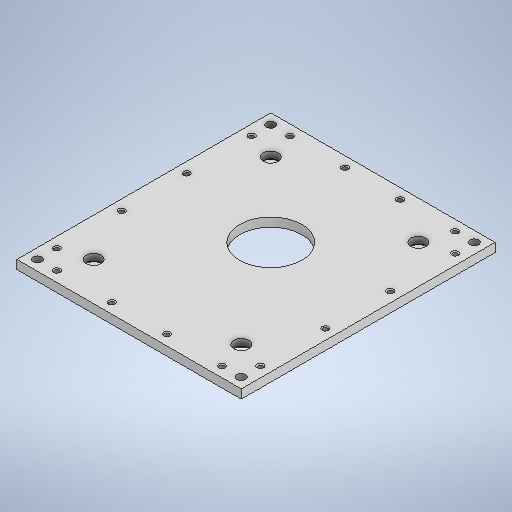
# Autodesk Inventor part: płyta_przednia
Saved by Autodesk Inventor 2025.2 (Build 292293000, 293)
## iProperties
Created: 2025-04-07
Part Number: płyta_przednia
Material: Ogólny
Document SubType Name: Modeling
Designer: Jan Bołtralik
Density: 1 g/cm^3
Appearance: Domyślna
Author: Jan Bołtralik
Autodesk Inventor part; units mm, degrees
ref_plane "YZ Plane" through (0, 0, 0) normal (1, 0, 0) x (0, 1, 0)
ref_plane "XZ Plane" through (0, 0, 0) normal (0, 1, 0) x (-1, 0, 0)
ref_plane "XY Plane" through (0, 0, 0) normal (0, 0, 1) x (1, 0, 0)
sketch "Szkic1" plane through (0, 0, 0) normal (0, 1, 0) x (-1, 0, 0)
  line L0 (0, 0) -> (-76, 0)
  line L1 (-76, 0) -> (-76, -86)
  line L2 (-76, -86) -> (0, -86)
  line L3 (0, -86) -> (0, 0)
  circle A0 centre (-38, -48) radius 10.5
  line L4 (-63, -13) -> (-13, -13) construction
  line L5 (-13, -13) -> (-13, -73) construction
  line L6 (-13, -73) -> (-63, -73) construction
  line L7 (-63, -73) -> (-63, -13) construction
  dimension "d23" = 76
  dimension "d24" = 86
  dimension "d25" = 21
  dimension "d26" = 38
  dimension "d27" = 38
  dimension "d28" = 50
  dimension "d29" = 60
  dimension "d30" = 13
  dimension "d31" = 13
  constraints: 16 end point, 4 parallel, 2 horizontal, 2 perpendicular, 1 centre point, 1 other
  measures "d23" distance of L2.end L1.end
  measures "d24" distance of L1.end L0.end
  measures "d25" diameter of A0
  measures "d26" distance from line of L3 A0.centre
  measures "d27" distance from line of L2 A0.centre
  measures "d28" distance of L5.end L6.end
  measures "d29" distance of L4.end L5.end
  measures "d30" distance between parallel lines of L2 L6
  measures "d31" distance between parallel lines of L1 L7
extrude "Wyciągnięcie proste1" add sketch "Szkic1" along normal blind 3
sketch "Szkic2" plane through (0, 0, 0) normal (0, -1, 0) x (1, 0, 0)
  line L0 (76, 0) -> (76, -86) construction
  line L1 (0, 0) -> (76, 0) construction
  line L2 (0, -86) -> (0, 0) construction
  line L3 (76, -86) -> (0, -86) construction
  circle A0 centre (38, -48) radius 10.5 construction
  line L4 (63, -13) -> (13, -13) construction
  line L5 (13, -13) -> (13, -73) construction
  line L6 (13, -73) -> (63, -73) construction
  line L7 (63, -73) -> (63, -13) construction
  dimension "d32" = 50
  dimension "d33" = 60
  dimension "d34" = 13
  dimension "d35" = 13
  constraints: 8 end point, 2 parallel, 1 horizontal, 1 perpendicular
  measures "d32" distance of L6.end L5.end
  measures "d33" distance of L5.end L4.end
  measures "d34" distance between parallel lines of L3 L6
  measures "d35" distance between parallel lines of L2 L5
hole "Otwór2" at (63, 0, -13) at (63, 0, -73) at (13, 0, -13) at (13, 0, -73) direction (0, 1, 0) diameter 5 end through all countersink diameter 6.5 countersink angle 90
sketch "Szkic5" plane through (0, 3, 0) normal (0, 1, 0) x (1, 0, 0)
  circle A0 centre (10, 3.5) radius 1.1 projected
  circle A1 centre (10, 82.5) radius 1.1 projected
  circle A2 centre (28.6667, 3.5) radius 1.1 projected
  circle A3 centre (28.6667, 82.5) radius 1.1 projected
  circle A4 centre (47.3333, 3.5) radius 1.1 projected
  circle A5 centre (47.3333, 82.5) radius 1.1 projected
  circle A6 centre (66, 3.5) radius 1.1 projected
  circle A7 centre (66, 82.5) radius 1.1 projected
  circle A8 centre (72.5, 10) radius 1.1 projected
  circle A9 centre (3.5, 10) radius 1.1 projected
  circle A10 centre (72.5, 32) radius 1.1 projected
  circle A11 centre (3.5, 32) radius 1.1 projected
  circle A12 centre (72.5, 54) radius 1.1 projected
  circle A13 centre (3.5, 54) radius 1.1 projected
  circle A14 centre (72.5, 76) radius 1.1 projected
  circle A15 centre (3.5, 76) radius 1.1 projected
  arc A16 (0, 10) -> (10, 0) centre (10, 10) ccw projected
  line L0 (66, 0) -> (10, 0) projected
  arc A17 (66, 0) -> (76, 10) centre (66, 10) ccw projected
  line L1 (76, 76) -> (76, 10) projected
  arc A18 (76, 76) -> (66, 86) centre (66, 76) ccw projected
  line L2 (10, 86) -> (66, 86) projected
  arc A19 (10, 86) -> (0, 76) centre (10, 76) ccw projected
  line L3 (0, 10) -> (0, 76) projected
  line L4 (6.5, 76) -> (6.5, 10) projected
  arc A20 (10, 79.5) -> (6.5, 76) centre (10, 76) ccw projected
  line L5 (66, 79.5) -> (10, 79.5) projected
  arc A21 (69.5, 76) -> (66, 79.5) centre (66, 76) ccw projected
  line L6 (69.5, 10) -> (69.5, 76) projected
  arc A22 (66, 6.5) -> (69.5, 10) centre (66, 10) ccw projected
  line L7 (10, 6.5) -> (66, 6.5) projected
  arc A23 (6.5, 10) -> (10, 6.5) centre (10, 10) ccw projected
hole "Otwór5" at (66, 3, -82.5) at (47.3333, 3, -82.5) at (28.6667, 3, -82.5) at (10, 3, -82.5) at (3.5, 3, -76) at (3.5, 3, -54) at (3.5, 3, -32) at (3.5, 3, -10) at (10, 3, -3.5) at (28.6667, 3, -3.5) at (47.3333, 3, -3.5) at (66, 3, -3.5) at (72.5, 3, -10) at (72.5, 3, -32) at (72.5, 3, -54) at (72.5, 3, -76) direction (0, -1, 0) diameter 1.567 depth 6.3 countersink diameter 2.2 countersink angle 90 thread size "M2x0.4" class "6H" standard "ISO Metric profile"
sketch "Sketch6" plane through (0, 0, 0) normal (0, -1, 0) x (1, 0, 0)
  circle A0 centre (72.5, -76) radius 0.7835 projected
  circle A1 centre (72.5, -54) radius 0.7835 projected
  circle A2 centre (72.5, -32) radius 0.7835 projected
  circle A3 centre (72.5, -10) radius 0.7835 projected
  circle A4 centre (66, -3.5) radius 0.7835 projected
  circle A5 centre (47.3333, -3.5) radius 0.7835 projected
  circle A6 centre (28.6667, -3.5) radius 0.7835 projected
  circle A7 centre (10, -3.5) radius 0.7835 projected
  circle A8 centre (3.5, -10) radius 0.7835 projected
  circle A9 centre (3.5, -32) radius 0.7835 projected
  circle A10 centre (3.5, -54) radius 0.7835 projected
  circle A11 centre (3.5, -76) radius 0.7835 projected
  circle A12 centre (10, -82.5) radius 0.7835 projected
  circle A13 centre (28.6667, -82.5) radius 0.7835 projected
  circle A14 centre (47.3333, -82.5) radius 0.7835 projected
  circle A15 centre (66, -82.5) radius 0.7835 projected
  circle A16 centre (13, -73) radius 3.25 projected
  circle A17 centre (13, -13) radius 3.25 projected
  circle A18 centre (63, -73) radius 3.25 projected
  circle A19 centre (63, -13) radius 3.25 projected
  line L0 (76, 0) -> (76, -86) projected
  line L1 (0, 0) -> (76, 0) projected
  line L2 (0, -86) -> (0, 0) projected
  line L3 (76, -86) -> (0, -86) projected
  circle A20 centre (38, -48) radius 10.5 projected
  line L4 (3.5, -3.5) -> (72.5, -3.5)
  line L5 (72.5, -3.5) -> (72.5, -82.5)
  line L6 (72.5, -82.5) -> (3.5, -82.5)
  line L7 (3.5, -82.5) -> (3.5, -3.5)
  constraints: 8 end point, 3 perpendicular, 1 horizontal
hole "Hole6" at (3.5, 0, -3.5) at (72.5, 0, -3.5) at (3.5, 0, -82.5) at (72.5, 0, -82.5) direction (0, 1, 0) diameter 2.85 end through all thread size "M3.5x0.6" class "6H" standard "ISO Metric profile"
